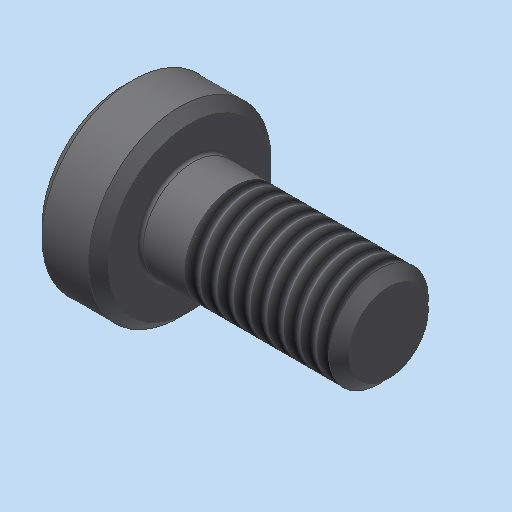
# Autodesk Inventor part: Zylinderschraube_DIN_7984___M3x6
Saved by Autodesk Inventor 2023.3 (Build 273359000, 359)
## iProperties
Shininess: 64.0
Length Units: 11269
Angle Units: 11279
Time Units: 11290
Mass Units: 11283
Length Display Precision: 3
Angle Display Precision: 2
Compacted: True
Part Number: Zylinderschraube_DIN_7984___M3x6
Document SubType Name: Modeling
Created: 2004-04-02
Material: xStahl_AnP_Dummymaterial
Description: =<RBPARTNOTITLE2>
Vendor: NORM8
Designer: S.Riedelsheimer
Manufacturer: Standard
Standards Organization: Custom
Density: 7.85 g/cm^3
Appearance: Stahl - normal AnP
Mass: 0.650305 g
Surface Area: 1.40493 cm^2
Volume: 0.0828414 cm^3
DOC_ID: 5 F45 Zylinderschraube_DIN_7984___M3x6
GAIN_REFID: 20__Zylinderschraube_DIN_7984___M3x6:81C07
Control State: 0
Master: False
Checked Out: False
CNS_NB: Zylinderschraube DIN 7984 - M3x6
CNS_NN: DIN 7984
CNS_NT: Zylinderschraube mit Innensechskant und niedrigem Kopf
CNS_NBSYN: Zylinderschraube DIN 7984 - $NENN.
CNS_LINA: Zylinderschraube DIN 7984 - M3x6
CNS_NENN: M3x6
CNS_D: 3.000
CNS_D3: 2.387
CNS_P: 0.500
CNS_L: 6.000
CNS_S: 2.000
CNS_DK: 5.500
CNS_K: 2.000
CNS_LS: 0.500
CNS_LG: 1.500
CNS_R: 0.100
CNS_T: 1.500
CNS_V: 0.300
CNS_KT: X
PSOL_IDENT_0: {C:\partsolutions8\data\23d-libs\bosch_bamberg\schrauben\zylinderschrauben\din_7984.prj},167 {M=Nenn
PSOL_IDENT_1: gewinde},{VTYP=3D},{NB=Zylinderschraube DIN 7984 - M3x6},{NN=DIN 7984},{DATE=4.12.2003},{GEOMDATE=04
PSOL_IDENT_2: .12.2003},{VERSION=v1},{LINEID=20},{LINESUBID=-1},{WBVAR=}  {NB=Zylinderschraube DIN 7984 - M3x6},{L
PSOL_IDENT_3: INA=Zylinderschraube DIN 7984 - M3x6},{KT=X},{IDNR=},{NENN=M3x6},{D=3.000},{D3=2.387},{P=0.500},{L=6
PSOL_IDENT_4: .000},{S=2.000},{DK=5.500},{K=2.000},{LS=0.500},{LG=1.500},{R=0.100},{T=1.500},{V=0.300}
DEF_STKID: T20938
Bezeichnung1: Zylinderschraube DIN 7984 - M3x6
Bezeichnung2: Zylinderschraube mit Innensechskant und
RBDRAWINGMISSINGSPEC: --
AnP_Kategorie: 4
RBPARTNOTITLE1: Hexagon socket head cap screws with low head
RBPARTNOTITLE2: Zylinderschrauben mit Innensechskant mit niedrigem Kopf
RBPARTMADEOF: DIN 7984 - M3x6 - 8.8 - verzinkt
Density: 0.0
Volumn: 0.0
Area: 0.0
PropertySet Name: Model Information
Title: Zylinderschraube DIN 7984 - M3x6
Author: S.Riedelsheimer
Keywords: =<RBPARTMADEOF>
Comments: =<RBSURFACE2>
Revision Number: 01
Autodesk Inventor part; units mm, degrees
sketch "Sketch_1" plane through (0, 0, 0) normal (0, 0, 1) x (1, 0, 0)
  line L0 (6, 0) -> (-2, 0)
  line L1 (-2, 0) -> (-2, 2.45)
  line L2 (-2, 2.45) -> (-1.7, 2.75)
  line L3 (-1.7, 2.75) -> (-0.3, 2.75)
  line L4 (-0.3, 2.75) -> (0, 2.45)
  line L5 (0, 2.45) -> (0, 1.6)
  arc A0 (0, 1.6) -> (0.1, 1.5) centre (0.1, 1.6) ccw
  line L6 (0.1, 1.5) -> (5.6935, 1.5)
  line L7 (5.6935, 1.5) -> (6, 1.1935)
  line L8 (6, 1.1935) -> (6, 0)
  line L9 (6, 0) -> (-2, 0)
  constraints: 20 end point, 2 point on circle, 1 centre point
revolve "Drehung1" add sketch "Sketch_1" angle 360 about axis through (6, 0, 0) along (1, 0, 0)
thread "Gewinde1" size "M3x0.5" class "6g" standard "ANSI Metric M Profile" length 4.3561
sketch "Sketch_2" plane through (-2, 0, 0) normal (1, 0, 0) x (0, 0, -1)
  line L0 (-1, 0.5774) -> (-1, -0.5774)
  line L1 (-1, -0.5774) -> (0, -1.1547)
  line L2 (0, -1.1547) -> (1, -0.5774)
  line L3 (1, -0.5774) -> (1, 0.5774)
  line L4 (1, 0.5774) -> (0, 1.1547)
  line L5 (0, 1.1547) -> (-1, 0.5774)
  constraints: 12 end point
extrude "Extrusion1" cut sketch "Sketch_2" along normal blind 1.5
ref_plane "IP1_XY" through (0, 0, 0) normal (1, 0, 0) x (0, 0, -1)
ref_plane "IP1_YZ" through (0, 0, 0) normal (0, 0, -1) x (0, 1, 0)
ref_plane "IP2_XY" through (-2, 0, 0) normal (1, 0, 0) x (0, 0, -1)
ref_plane "IP2_YZ" through (-2, 0, 0) normal (0, 0, -1) x (0, 1, 0)
ref_plane "IP3_XY" through (6, 0, 0) normal (1, 0, 0) x (0, 0, -1)
ref_plane "IP3_YZ" through (6, 0, 0) normal (0, 0, -1) x (0, 1, 0)
